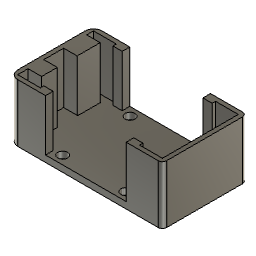
Machine2 (Autodesk Fusion 360 archive; units mm, degrees)
design "9VBatteryBox"
Autodesk Fusion 360 part; units mm, degrees
sketch "スケッチ1" plane through (0, 0, 0) normal (0, 0, 1) x (1, 0, 0)
  line L0 (144.9399, 9.1944) -> (279.0278, 9.1944)
  line L1 (203.6278, 43.1944) -> (203.6278, 34.9671)
  line L2 (159.4515, 43.1944) -> (104.8278, 43.1944)
  line L3 (104.8278, 39.3843) -> (144.9399, 39.3843)
  line L4 (287, 55) -> (292, 55)
  line L5 (159.4515, 43.1944) -> (287, 43.1944)
  line L6 (144.9399, 39.3843) -> (144.9399, 4.9444)
  line L7 (144.9399, 39.3843) -> (144.9399, 43.1944)
  line L8 (117.0478, 43.1944) -> (117.0478, 30.8655)
  line L9 (238.7084, 9.1944) -> (238.7084, 4.9444)
  line L10 (104.8278, 34.9671) -> (144.9399, 34.9671)
  line L11 (104.8278, 30.8655) -> (144.9399, 30.8655)
  line L12 (134.0867, 43.1944) -> (134.0867, 30.8655)
  line L13 (104.8278, 18.8579) -> (144.9399, 18.8579)
  line L14 (144.9399, 34.9671) -> (203.6278, 34.9671)
  line L15 (203.6278, 34.9671) -> (203.6278, 9.1944)
  line L16 (203.6278, 21.9444) -> (292, 21.9444)
  line L17 (188.3904, 43.1944) -> (188.3904, 34.9671)
  line L18 (257.9467, 4.9444) -> (257.9467, 9.1944)
  line L19 (104.8278, 43.1944) -> (104.8278, 7.374)
  line L20 (203.6278, 9.1944) -> (203.6278, 5)
  line L21 (292.0278, 13.4444) -> (279.0278, 13.4444)
  line L22 (292, 5) -> (292, 77.25)
  line L23 (279.0278, 21.9444) -> (279.0278, 4.9444)
  line L24 (98.5, 10) -> (104.8278, 10)
  line L25 (104.8278, 7.374) -> (104.8278, 5)
  line L26 (287, 200) -> (10, 200)
  line L27 (292, 205) -> (5, 205)
  line L28 (10, 200) -> (10, 10)
  line L29 (5, 205) -> (5, 5)
  line L30 (10, 55) -> (5, 55)
  line L31 (5, 105) -> (15, 105)
  line L32 (5, 5) -> (292, 5)
  line L33 (10, 10) -> (98.5, 10)
  line L34 (48.5, 5) -> (48.5, 10)
  line L35 (98.5, 10) -> (98.5, 5)
  line L36 (10, 155) -> (5, 155)
  line L37 (48.5, 200) -> (48.5, 205)
  line L38 (98.5, 205) -> (98.5, 200)
  line L39 (148.5, 205) -> (148.5, 195)
  line L40 (287, 43.1944) -> (287, 200)
  line L41 (292, 77.25) -> (292, 205)
  line L42 (292, 105) -> (282, 105)
  line L43 (198.5, 205) -> (198.5, 200)
  line L44 (248.5, 200) -> (248.5, 205)
  line L45 (287, 155) -> (292, 155)
  line L46 (106.6389, 30.0526) -> (114.8305, 30.0526)
  line L47 (115.4156, 29.4675) -> (115.4156, 23.0314)
  line L48 (115.4156, 23.0314) -> (114.6794, 23.0314)
  line L49 (112.2568, 23.0314) -> (109.2123, 23.0314)
  line L50 (106.7919, 23.0314) -> (106.0539, 23.0314)
  line L51 (106.0539, 23.0314) -> (106.0539, 29.4675)
  spline S0 degree 3 poles (114.8305, 30.0526) (115.1527, 30.0526) (115.4156, 29.7898) (115.4156, 29.4675) knots 0.055556 0.055556 0.055556 0.055556 0.111111 0.111111 0.111111 0.111111
  spline S1 degree 3 poles (114.6794, 23.0314) (114.6946, 23.0993) (114.7024, 23.1717) (114.7021, 23.2489) knots 0.222222 0.222222 0.222222 0.222222 0.277778 0.277778 0.277778 0.277778
  spline S2 degree 3 poles (114.7021, 23.2489) (114.7044, 23.8132) (114.2828, 24.1347) (113.5747, 24.1481) knots 0.277778 0.277778 0.277778 0.277778 0.333333 0.333333 0.333333 0.333333
  spline S3 degree 3 poles (113.5747, 24.1481) (112.9581, 24.1595) (112.3453, 23.8174) (112.1979, 23.7292) knots 0.333333 0.333333 0.333333 0.333333 0.388889 0.388889 0.388889 0.388889
  spline S4 degree 3 poles (112.1979, 23.7292) (112.2465, 23.5795) (112.273, 23.4198) (112.273, 23.2538) knots 0.388889 0.388889 0.388889 0.388889 0.444444 0.444444 0.444444 0.444444
  spline S5 degree 3 poles (112.273, 23.2538) (112.273, 23.1782) (112.2673, 23.104) (112.2568, 23.0314) knots 0.444444 0.444444 0.444444 0.444444 0.5 0.5 0.5 0.5
  spline S6 degree 3 poles (109.2123, 23.0314) (109.2017, 23.104) (109.1963, 23.1782) (109.1963, 23.2538) knots 0.555556 0.555556 0.555556 0.555556 0.611111 0.611111 0.611111 0.611111
  spline S7 degree 3 poles (109.1963, 23.2538) (109.1963, 23.4229) (109.2237, 23.5853) (109.2741, 23.7373) knots 0.611111 0.611111 0.611111 0.611111 0.666667 0.666667 0.666667 0.666667
  spline S8 degree 3 poles (109.2741, 23.7373) (109.1314, 23.823) (108.515, 24.1692) (107.8945, 24.1579) knots 0.666667 0.666667 0.666667 0.666667 0.722222 0.722222 0.722222 0.722222
  spline S9 degree 3 poles (107.8945, 24.1579) (107.1865, 24.1445) (106.7649, 23.823) (106.7672, 23.2587) knots 0.722222 0.722222 0.722222 0.722222 0.777778 0.777778 0.777778 0.777778
  spline S10 degree 3 poles (106.7672, 23.2587) (106.7669, 23.1778) (106.7752, 23.1021) (106.7919, 23.0314) knots 0.777778 0.777778 0.777778 0.777778 0.833333 0.833333 0.833333 0.833333
  spline S11 degree 3 poles (106.0539, 29.4675) (106.0539, 29.7898) (106.3167, 30.0526) (106.6389, 30.0526) knots 0.944444 0.944444 0.944444 0.944444 1 1 1 1
  spline S12 degree 3 poles (109.3634, 23.9517) (109.1948, 23.9942) (108.522, 24.1858) (108.0949, 24.6289) knots 0 0 0 0 0.2 0.2 0.2 0.2
  spline S13 degree 3 poles (108.0949, 24.6289) (107.6036, 25.139) (107.5329, 25.6644) (107.9335, 26.0619) knots 0.2 0.2 0.2 0.2 0.4 0.4 0.4 0.4
  spline S14 degree 3 poles (107.9335, 26.0619) (108.3311, 26.4624) (108.8564, 26.3917) (109.3665, 25.9005) knots 0.4 0.4 0.4 0.4 0.6 0.6 0.6 0.6
  spline S15 degree 3 poles (109.3665, 25.9005) (109.8123, 25.4709) (110.0034, 24.7921) (110.0444, 24.6287) knots 0.6 0.6 0.6 0.6 0.8 0.8 0.8 0.8
  spline S16 degree 3 poles (110.0444, 24.6287) (109.7516, 24.4814) (109.5122, 24.2435) (109.3634, 23.9517) knots 0.8 0.8 0.8 0.8 1 1 1 1
  spline S17 degree 3 poles (110.2591, 24.7171) (110.1709, 24.8646) (109.829, 25.4771) (109.8404, 26.094) knots 0 0 0 0 0.166667 0.166667 0.166667 0.166667
  spline S18 degree 3 poles (109.8404, 26.094) (109.8538, 26.8019) (110.1752, 27.2235) (110.7395, 27.2213) knots 0.166667 0.166667 0.166667 0.166667 0.333333 0.333333 0.333333 0.333333
  spline S19 degree 3 poles (110.7395, 27.2213) (111.3039, 27.2235) (111.6253, 26.8019) (111.6387, 26.094) knots 0.333333 0.333333 0.333333 0.333333 0.5 0.5 0.5 0.5
  spline S20 degree 3 poles (111.6387, 26.094) (111.65, 25.4734) (111.3039, 24.8569) (111.2184, 24.7144) knots 0.5 0.5 0.5 0.5 0.666667 0.666667 0.666667 0.666667
  spline S21 degree 3 poles (111.2184, 24.7144) (111.0662, 24.7647) (110.9035, 24.7921) (110.7347, 24.7921) knots 0.666667 0.666667 0.666667 0.666667 0.833333 0.833333 0.833333 0.833333
  spline S22 degree 3 poles (110.7347, 24.7921) (110.5688, 24.7921) (110.4089, 24.7658) (110.2591, 24.7171) knots 0.833333 0.833333 0.833333 0.833333 1 1 1 1
  spline S23 degree 3 poles (111.4325, 24.6249) (111.4749, 24.7933) (111.6665, 25.4664) (112.1097, 25.8936) knots 0 0 0 0 0.2 0.2 0.2 0.2
  spline S24 degree 3 poles (112.1097, 25.8936) (112.6197, 26.3848) (113.1452, 26.4555) (113.5426, 26.0549) knots 0.2 0.2 0.2 0.2 0.4 0.4 0.4 0.4
  spline S25 degree 3 poles (113.5426, 26.0549) (113.9432, 25.6574) (113.8724, 25.132) (113.3813, 24.6219) knots 0.4 0.4 0.4 0.4 0.6 0.6 0.6 0.6
  spline S26 degree 3 poles (113.3813, 24.6219) (112.9516, 24.1761) (112.2728, 23.9849) (112.1096, 23.9441) knots 0.6 0.6 0.6 0.6 0.8 0.8 0.8 0.8
  spline S27 degree 3 poles (112.1096, 23.9441) (111.9622, 24.2367) (111.7244, 24.476) (111.4325, 24.6249) knots 0.8 0.8 0.8 0.8 1 1 1 1
  line L52 (223.6183, 98.7307) -> (218.9513, 101.4249)
  line L53 (274.9744, 80.257) -> (274.9744, 93.3217)
  line L54 (178.3634, 124.8558) -> (173.6965, 127.5499)
  line L55 (159.2013, 133.9005) -> (159.2013, 100.259)
  spline S28 degree 3 poles (177.0807, 117.3528) (177.1468, 117.3877) (177.3767, 117.5094) (177.7645, 117.7871) (178.2366, 118.1785) (178.689, 118.628) (179.1161, 119.1237) (179.512, 119.6598) (179.8714, 120.2282) (180.1894, 120.8211) (180.4616, 121.4303) (180.684, 122.0475) (180.8534, 122.6643) (180.966, 123.2721) (181.0116, 123.7473) (181.0152, 124.0151) (181.0162, 124.0928) knots 0 0 0 0 0.031575 0.109833 0.188038 0.266123 0.344083 0.421947 0.499754 0.577553 0.655385 0.733293 0.811326 0.889534 0.967956 1 1 1 1
  spline S29 degree 3 poles (181.0162, 124.0928) (181.0145, 124.1922) (181.0095, 124.4798) (180.9541, 124.9309) (180.8293, 125.4266) (180.6418, 125.8715) (180.3971, 126.2601) (180.0948, 126.5734) (179.8692, 126.76) (179.7374, 126.82) (179.7335, 126.8218) knots 0 0 0 0 0.082093 0.237396 0.392753 0.547179 0.699572 0.849018 0.995492 1 1 1 1
  line L56 (179.739, 126.82) -> (172.9508, 130.7388)
  spline S30 degree 3 poles (177.0233, 125.6294) (177.0895, 125.672) (177.2938, 125.8032) (177.6296, 125.954) (178.0198, 126.082) (178.3856, 126.1403) (178.7205, 126.1324) (178.9934, 126.0774) (179.139, 125.999) (179.1983, 125.9671) knots 0 0 0 0 0.077027 0.237559 0.397851 0.558376 0.720409 0.8862 1 1 1 1
  line L57 (191.7004, 133.5787) -> (196.8468, 140.1409)
  line L58 (191.8248, 126.7682) -> (191.7058, 133.5856)
  line L59 (196.7999, 140.081) -> (201.8926, 139.7804)
  line L60 (191.1308, 126.0582) -> (196.9749, 125.7132)
  line L61 (202.7184, 132.9443) -> (202.5866, 140.4904)
  line L62 (197.0978, 125.7686) -> (202.7132, 132.9287)
  line L63 (174.9593, 93.4835) -> (174.9593, 123.3689)
  line L64 (174.9593, 93.4835) -> (215.5473, 70.0526)
  line L65 (215.5473, 99.9379) -> (215.5473, 70.0526)
  line L66 (215.5473, 99.9379) -> (231.5279, 90.7125)
  line L67 (231.5279, 70.1357) -> (231.5279, 90.7125)
  line L68 (231.6693, 70.0541) -> (231.5279, 70.1357)
  line L69 (231.6693, 56.9894) -> (231.6693, 70.0541)
  line L70 (160.9586, 97.8098) -> (231.6693, 56.9894)
  line L71 (160.9586, 131.4513) -> (160.9586, 97.8098)
  line L72 (160.9586, 131.4513) -> (174.9593, 123.3689)
  line L73 (233.6492, 71.3603) -> (231.5279, 70.1357)
  line L74 (233.6492, 91.9371) -> (231.5279, 90.7125)
  line L75 (233.6492, 71.3603) -> (233.6492, 91.9371)
  line L76 (222.3355, 98.4684) -> (233.6492, 91.9371)
  line L77 (215.5473, 99.9379) -> (217.9514, 101.3258)
  line L78 (222.6183, 98.6317) -> (217.9514, 101.3258)
  line L79 (222.3355, 98.4684) -> (222.6183, 98.6317)
  arc A0 (224.0325, 97.815) -> (222.6183, 98.6317) centre (223.1704, 97.9549) ccw
  line L80 (224.0325, 97.4887) -> (224.0325, 97.815)
  arc A1 (218.9513, 101.4249) -> (217.9514, 101.3258) centre (218.5373, 100.5081) ccw
  line L81 (235.9119, 70.0541) -> (235.9119, 56.9894)
  arc A2 (231.6693, 56.9894) -> (235.9119, 56.9894) centre (233.7906, 61.0611) ccw
  arc A3 (231.6693, 70.0541) -> (235.9119, 70.0541) centre (233.7906, 74.1257) ccw
  line L82 (273.9543, 94.6279) -> (271.833, 93.4033)
  line L83 (273.9543, 94.6279) -> (274.0957, 94.5463)
  arc A4 (274.0957, 92.0971) -> (274.0957, 94.5463) centre (273.6179, 93.3217) ccw
  line L84 (274.0957, 92.0971) -> (235.9119, 70.0541)
  line L85 (271.9744, 93.3217) -> (233.7906, 71.2787)
  line L86 (271.833, 93.4033) -> (271.9744, 93.3217)
  line L87 (233.7906, 71.2787) -> (233.6492, 71.3603)
  line L88 (235.9119, 56.9894) -> (274.0957, 79.0324)
  line L89 (274.0957, 79.0324) -> (274.0957, 92.0971)
  line L90 (199.1424, 126.0581) -> (177.0807, 113.3222)
  line L91 (215.2644, 116.7511) -> (199.1424, 126.0581)
  line L92 (215.2644, 116.7511) -> (217.3857, 117.9757)
  line L93 (255.8524, 95.7694) -> (217.3857, 117.9757)
  line L94 (263.9121, 88.6674) -> (255.8524, 93.3202)
  line L95 (174.9593, 93.4835) -> (177.0807, 94.7081)
  line L96 (181.5402, 91.7624) -> (182.0222, 91.5942)
  line L97 (180.1208, 93.1179) -> (180.2445, 92.8007)
  line L98 (180.7462, 92.2208) -> (181.1112, 91.9731)
  line L99 (186.5059, 92.2878) -> (186.7777, 92.5726)
  line L100 (186.1586, 92.0318) -> (186.5059, 92.2878)
  line L101 (182.1496, 95.2443) -> (181.6562, 95.0874)
  line L102 (184.355, 95.373) -> (183.7974, 95.4186)
  line L103 (186.252, 94.7109) -> (185.8537, 94.9409)
  line L104 (185.2746, 91.632) -> (185.7446, 91.8113)
  line L105 (182.6802, 95.3535) -> (182.1496, 95.2443)
  line L106 (183.2342, 95.4121) -> (182.6802, 95.3535)
  line L107 (187.0797, 93.5238) -> (187.0005, 93.8458)
  line L108 (185.7446, 91.8113) -> (186.1586, 92.0318)
  line L109 (184.8928, 95.2762) -> (184.355, 95.373)
  line L110 (183.7974, 95.4186) -> (183.2342, 95.4121)
  line L111 (182.5448, 91.4728) -> (183.0943, 91.4014)
  line L112 (187.0005, 93.8458) -> (186.8329, 94.1562)
  line L113 (180.5203, 94.3766) -> (180.2892, 94.0801)
  line L114 (186.5813, 94.4471) -> (186.252, 94.7109)
  line L115 (186.9668, 92.8789) -> (187.0683, 93.1987)
  line L116 (184.761, 91.4986) -> (185.2746, 91.632)
  line L117 (183.6565, 91.3817) -> (184.2169, 91.4144)
  line L118 (180.0867, 93.4425) -> (180.1208, 93.1179)
  line L119 (181.1112, 91.9731) -> (181.5402, 91.7624)
  line L120 (183.0943, 91.4014) -> (183.6565, 91.3817)
  line L121 (180.4548, 92.4991) -> (180.7462, 92.2208)
  line L122 (186.7777, 92.5726) -> (186.9668, 92.8789)
  line L123 (184.2169, 91.4144) -> (184.761, 91.4986)
  line L124 (181.6562, 95.0874) -> (181.2128, 94.8869)
  line L125 (180.1434, 93.766) -> (180.0867, 93.4425)
  line L126 (185.8537, 94.9409) -> (185.3967, 95.1309)
  line L127 (186.8329, 94.1562) -> (186.5813, 94.4471)
  line L128 (187.0683, 93.1987) -> (187.0797, 93.5238)
  line L129 (181.2128, 94.8869) -> (180.8309, 94.6479)
  line L130 (185.3967, 95.1309) -> (184.8928, 95.2762)
  line L131 (180.2892, 94.0801) -> (180.1434, 93.766)
  line L132 (180.8309, 94.6479) -> (180.5203, 94.3766)
  line L133 (180.2445, 92.8007) -> (180.4548, 92.4991)
  line L134 (182.0222, 91.5942) -> (182.5448, 91.4728)
  arc A5 (212.931, 73.6039) -> (215.5473, 73.0138) centre (215.3371, 78.1768) ccw
  line L135 (211.9066, 75.0733) -> (211.9406, 74.7488)
  line L136 (211.9406, 74.7488) -> (212.0643, 74.4315)
  line L137 (215.054, 77.0429) -> (214.5, 76.9843)
  line L138 (212.6507, 76.2787) -> (212.3401, 76.0075)
  line L139 (214.5, 76.9843) -> (213.9694, 76.8751)
  line L140 (215.5473, 77.0515) -> (215.054, 77.0429)
  line L141 (212.566, 73.8516) -> (212.931, 73.6039)
  line L142 (212.2746, 74.1299) -> (212.566, 73.8516)
  line L143 (212.0643, 74.4315) -> (212.2746, 74.1299)
  line L144 (212.109, 75.7109) -> (211.9632, 75.3968)
  line L145 (213.476, 76.7183) -> (213.0326, 76.5177)
  line L146 (212.3401, 76.0075) -> (212.109, 75.7109)
  line L147 (211.9632, 75.3968) -> (211.9066, 75.0733)
  line L148 (213.0326, 76.5177) -> (212.6507, 76.2787)
  line L149 (213.9694, 76.8751) -> (213.476, 76.7183)
  line L150 (251.5055, 93.0359) -> (251.9195, 93.2564)
  line L151 (252.8406, 94.7484) -> (252.7614, 95.0704)
  line L152 (252.7614, 95.0704) -> (252.5939, 95.3808)
  line L153 (252.5939, 95.3808) -> (252.3422, 95.6717)
  line L154 (245.9043, 94.9906) -> (245.8477, 94.6671)
  line L155 (247.4172, 96.3121) -> (246.9738, 96.1115)
  line L156 (248.8552, 92.626) -> (249.4174, 92.6063)
  line L157 (247.7832, 92.8188) -> (248.3057, 92.6974)
  line L158 (246.2813, 95.6012) -> (246.0501, 95.3047)
  line L159 (249.5583, 96.6433) -> (248.9951, 96.6367)
  line L160 (252.5386, 93.7972) -> (252.7277, 94.1035)
  line L161 (247.9105, 96.4689) -> (247.4172, 96.3121)
  line L162 (252.013, 95.9356) -> (251.6147, 96.1655)
  line L163 (252.7277, 94.1035) -> (252.8292, 94.4233)
  line L164 (251.0356, 92.8566) -> (251.5055, 93.0359)
  line L165 (250.5219, 92.7232) -> (251.0356, 92.8566)
  line L166 (247.3011, 92.987) -> (247.7832, 92.8188)
  line L167 (246.0501, 95.3047) -> (245.9043, 94.9906)
  line L168 (252.8292, 94.4233) -> (252.8406, 94.7484)
  line L169 (249.9779, 92.639) -> (250.5219, 92.7232)
  line L170 (245.8477, 94.6671) -> (245.8817, 94.3426)
  line L171 (246.5071, 93.4454) -> (246.8721, 93.1977)
  line L172 (251.9195, 93.2564) -> (252.2669, 93.5124)
  line L173 (249.4174, 92.6063) -> (249.9779, 92.639)
  line L174 (248.3057, 92.6974) -> (248.8552, 92.626)
  line L175 (246.9738, 96.1115) -> (246.5918, 95.8725)
  line L176 (248.9951, 96.6367) -> (248.4411, 96.5781)
  line L177 (252.2669, 93.5124) -> (252.5386, 93.7972)
  line L178 (246.2157, 93.7237) -> (246.5071, 93.4454)
  line L179 (246.8721, 93.1977) -> (247.3011, 92.987)
  line L180 (251.1577, 96.3555) -> (250.6537, 96.5008)
  line L181 (246.5918, 95.8725) -> (246.2813, 95.6012)
  line L182 (250.6537, 96.5008) -> (250.116, 96.5976)
  line L183 (250.116, 96.5976) -> (249.5583, 96.6433)
  line L184 (245.8817, 94.3426) -> (246.0054, 94.0253)
  line L185 (246.0054, 94.0253) -> (246.2157, 93.7237)
  line L186 (248.4411, 96.5781) -> (247.9105, 96.4689)
  line L187 (252.3422, 95.6717) -> (252.013, 95.9356)
  line L188 (251.6147, 96.1655) -> (251.1577, 96.3555)
  line L189 (214.0279, 113.0363) -> (214.0619, 112.7117)
  line L190 (214.772, 114.2417) -> (214.4615, 113.9704)
  line L191 (214.4615, 113.9704) -> (214.2303, 113.6739)
  line L192 (220.0997, 111.6256) -> (220.4471, 111.8816)
  line L193 (218.2962, 114.9668) -> (217.7385, 115.0124)
  line L194 (216.0907, 114.8381) -> (215.5973, 114.6812)
  line L195 (214.6873, 111.8146) -> (215.0523, 111.5669)
  line L196 (214.2303, 113.6739) -> (214.0845, 113.3598)
  line L197 (218.8339, 114.87) -> (218.2962, 114.9668)
  line L198 (216.6213, 114.9473) -> (216.0907, 114.8381)
  line L199 (214.3959, 112.0929) -> (214.6873, 111.8146)
  line L200 (220.7741, 113.75) -> (220.5224, 114.0409)
  line L201 (219.3378, 114.7247) -> (218.8339, 114.87)
  line L202 (215.154, 114.4807) -> (214.772, 114.2417)
  line L203 (214.0619, 112.7117) -> (214.1856, 112.3945)
  line L204 (219.7949, 114.5347) -> (219.3378, 114.7247)
  line L205 (220.9416, 113.4396) -> (220.7741, 113.75)
  line L206 (217.7385, 115.0124) -> (217.1753, 115.0059)
  line L207 (214.0845, 113.3598) -> (214.0279, 113.0363)
  line L208 (214.1856, 112.3945) -> (214.3959, 112.0929)
  line L209 (217.1753, 115.0059) -> (216.6213, 114.9473)
  line L210 (215.5973, 114.6812) -> (215.154, 114.4807)
  line L211 (220.1932, 114.3047) -> (219.7949, 114.5347)
  line L212 (220.5224, 114.0409) -> (220.1932, 114.3047)
  line L213 (219.6857, 111.4051) -> (220.0997, 111.6256)
  line L214 (217.0354, 110.9952) -> (217.5976, 110.9755)
  line L215 (218.7021, 111.0924) -> (219.2158, 111.2258)
  line L216 (215.0523, 111.5669) -> (215.4813, 111.3562)
  line L217 (217.5976, 110.9755) -> (218.1581, 111.0082)
  line L218 (219.2158, 111.2258) -> (219.6857, 111.4051)
  line L219 (218.1581, 111.0082) -> (218.7021, 111.0924)
  line L220 (220.9079, 112.4727) -> (221.0094, 112.7925)
  line L221 (220.4471, 111.8816) -> (220.7188, 112.1664)
  line L222 (215.4813, 111.3562) -> (215.9634, 111.188)
  line L223 (216.4859, 111.0666) -> (217.0354, 110.9952)
  line L224 (215.9634, 111.188) -> (216.4859, 111.0666)
  line L225 (220.7188, 112.1664) -> (220.9079, 112.4727)
  line L226 (221.0208, 113.1176) -> (220.9416, 113.4396)
  line L227 (221.0094, 112.7925) -> (221.0208, 113.1176)
  line L228 (273.9543, 115.2048) -> (257.9737, 124.4302)
  line L229 (273.9543, 115.2048) -> (271.833, 113.9802)
  line L230 (271.833, 113.9802) -> (260.5193, 120.5114)
  line L231 (260.2364, 120.3481) -> (260.5193, 120.5114)
  line L232 (255.5695, 123.0423) -> (260.2364, 120.3481)
  line L233 (255.5695, 123.0423) -> (257.9737, 124.4302)
  line L234 (271.833, 113.9802) -> (271.833, 93.4033)
  line L235 (255.8524, 93.3202) -> (255.8524, 115.8568)
  line L236 (260.5193, 113.4892) -> (260.5193, 120.5114)
  line L237 (273.9543, 115.2048) -> (273.9543, 94.6279)
  arc A6 (215.5473, 73.2954) -> (214.1149, 73.1546) centre (215.3976, 67.4618) ccw
  arc A7 (260.2364, 120.3481) -> (258.8222, 117.8987) centre (261.8926, 117.7589) ccw
  line L238 (258.8222, 117.8987) -> (254.1553, 120.5928)
  arc A8 (255.5695, 123.0423) -> (254.1553, 120.5928) centre (257.2257, 120.4531) ccw
  line L239 (260.2364, 113.3259) -> (260.5193, 113.4892)
  line L240 (258.8222, 117.4087) -> (260.2364, 113.3259)
  line L241 (258.8222, 117.4087) -> (258.8222, 117.8987)
  line L242 (254.1553, 120.1029) -> (258.8222, 117.4087)
  line L243 (254.1553, 120.1029) -> (254.1553, 120.5928)
  line L244 (260.2364, 113.3259) -> (255.5695, 116.02)
  line L245 (255.5695, 116.02) -> (254.1553, 120.1029)
  arc A9 (274.0957, 79.0324) -> (274.9744, 80.257) centre (273.4748, 80.4055) ccw
  line L246 (177.3635, 117.7345) -> (178.7777, 123.4502)
  line L247 (177.0807, 117.5712) -> (177.3635, 117.7345)
  line L248 (177.0807, 94.7081) -> (177.0807, 117.5712)
  line L249 (177.3635, 124.7568) -> (174.9593, 123.3689)
  arc A10 (178.7777, 123.9401) -> (177.3635, 124.7568) centre (177.9156, 124.0799) ccw
  line L250 (178.7777, 123.4502) -> (178.7777, 123.9401)
  arc A11 (160.9586, 136.3497) -> (160.9586, 131.4513) centre (161.8882, 133.9005) ccw
  line L251 (194.8997, 155.9435) -> (160.9586, 136.3497)
  arc A12 (203.385, 155.9435) -> (194.8997, 155.9435) centre (199.1424, 147.7553) ccw
  line L252 (217.3857, 147.8611) -> (214.9816, 146.4732)
  line L253 (210.3147, 149.1674) -> (214.9816, 146.4732)
  line L254 (210.5975, 149.3306) -> (210.3147, 149.1674)
  line L255 (210.5975, 149.3306) -> (199.1424, 155.9435)
  line L256 (199.1424, 155.9435) -> (160.9586, 133.9005)
  line L257 (160.9586, 133.9005) -> (172.4138, 127.2876)
  line L258 (172.6966, 127.4509) -> (172.4138, 127.2876)
  line L259 (177.3635, 124.7568) -> (172.6966, 127.4509)
  line L260 (217.3857, 147.8611) -> (203.385, 155.9435)
  arc A13 (173.6965, 127.5499) -> (172.6966, 127.4509) centre (173.2824, 126.6331) ccw
  arc A14 (159.2013, 100.259) -> (160.9586, 97.8098) centre (162.217, 100.5678) ccw
  line L261 (195.6803, 144.6252) -> (189.8164, 144.9714)
  line L262 (189.8164, 144.9714) -> (184.0861, 137.6647)
  line L263 (184.0861, 137.6647) -> (184.2197, 130.012)
  line L264 (199.1424, 155.9435) -> (199.1424, 142.6266)
  line L265 (199.1424, 128.3756) -> (199.1424, 126.0581)
  arc A15 (172.9508, 130.7388) -> (168.7788, 129.386) centre (171.8313, 127.0816) ccw
  arc A16 (184.877, 91.5238) -> (182.2951, 91.5238) centre (183.586, 85.8157) ccw
  arc A17 (250.6379, 92.7484) -> (248.056, 92.7484) centre (249.347, 87.0403) ccw
  line L266 (179.239, 125.954) -> (179.195, 125.9784)
  arc A18 (214.9816, 146.4732) -> (213.5674, 144.0237) centre (216.6378, 143.884) ccw
  line L267 (213.5674, 144.0237) -> (208.9005, 146.7179)
  arc A19 (210.3147, 149.1674) -> (208.9005, 146.7179) centre (211.9709, 146.5781) ccw
  line L268 (215.2644, 139.6142) -> (215.2644, 116.7511)
  line L269 (214.9816, 139.451) -> (215.2644, 139.6142)
  line L270 (213.5674, 143.5338) -> (214.9816, 139.451)
  line L271 (213.5674, 143.5338) -> (213.5674, 144.0237)
  line L272 (217.3857, 147.8611) -> (217.3857, 117.9757)
  line L273 (196.894, 140.516) -> (191.4432, 133.5658)
  ellipse E0 centre (191.1603, 133.7291) end of major axis (191.5614, 133.5945) minor radius 0.0991 (190.8743, 133.746) -> (191.4432, 133.5658) ccw
  line L274 (190.8743, 133.746) -> (196.6046, 141.0526)
  ellipse E1 centre (196.6111, 140.6793) end of major axis (196.433, 141.0745) minor radius 0.2411 (196.894, 140.516) -> (196.6046, 141.0526) ccw
  line L275 (196.6046, 141.0526) -> (189.8164, 144.9714)
  line L276 (190.8743, 133.746) -> (184.0861, 137.6647)
  line L277 (197.1449, 126.1438) -> (191.7101, 126.4646)
  line L278 (202.4559, 132.9158) -> (197.1449, 126.1438)
  line L279 (202.3321, 140.0086) -> (202.4559, 132.9158)
  line L280 (196.8972, 140.3294) -> (202.3321, 140.0086)
  line L281 (191.5862, 133.5574) -> (196.8972, 140.3294)
  line L282 (191.7101, 126.4646) -> (191.5862, 133.5574)
  line L283 (202.4718, 140.1868) -> (196.894, 140.516)
  line L284 (202.599, 132.9073) -> (202.4718, 140.1868)
  line L285 (197.1482, 125.9571) -> (202.599, 132.9073)
  line L286 (191.5703, 126.2864) -> (197.1482, 125.9571)
  line L287 (191.4432, 133.5658) -> (191.5703, 126.2864)
  line L288 (208.9005, 146.2279) -> (213.5674, 143.5338)
  line L289 (208.9005, 146.2279) -> (208.9005, 146.7179)
  ellipse E2 centre (191.3034, 133.7207) end of major axis (191.7044, 133.5861) minor radius 0.0991 (191.5862, 133.5574) -> (191.7004, 133.5787) ccw
  ellipse E3 centre (196.6144, 140.4927) end of major axis (196.4363, 140.8879) minor radius 0.2411 (196.8468, 140.1409) -> (196.8972, 140.3294) ccw
  line L290 (214.9816, 139.451) -> (210.3147, 142.1451)
  line L291 (210.3147, 142.1451) -> (208.9005, 146.2279)
  ellipse E4 centre (191.2874, 126.4496) end of major axis (191.6177, 126.7664) minor radius 0.32 (191.0079, 126.0932) -> (191.5703, 126.2864) ccw
  line L292 (191.0079, 126.0932) -> (190.8743, 133.746)
  line L293 (191.0079, 126.0932) -> (184.2197, 130.012)
  ellipse E5 centre (191.4272, 126.6279) end of major axis (191.7574, 126.9446) minor radius 0.32 (191.7101, 126.4646) -> (191.8248, 126.7682) ccw
  line L294 (196.6046, 141.0526) -> (202.4685, 140.7065)
  ellipse E6 centre (202.189, 140.3501) end of major axis (202.5192, 140.6669) minor radius 0.32 (202.4718, 140.1868) -> (202.4685, 140.7065) ccw
  line L295 (202.4685, 140.7065) -> (195.6803, 144.6252)
  ellipse E7 centre (202.0492, 140.1718) end of major axis (202.3795, 140.4886) minor radius 0.32 (201.8926, 139.7804) -> (202.3321, 140.0086) ccw
  ellipse E8 centre (196.8653, 126.1204) end of major axis (196.6872, 126.5156) minor radius 0.2411 (196.9749, 125.7132) -> (197.1482, 125.9571) ccw
  ellipse E9 centre (196.8621, 126.307) end of major axis (196.684, 126.7023) minor radius 0.2411 (197.1449, 126.1438) -> (196.8556, 126.6803) ccw
  line L296 (196.8556, 126.6803) -> (191.7751, 129.6132)
  ellipse E10 centre (202.1731, 133.079) end of major axis (202.5741, 132.9444) minor radius 0.0991 (201.887, 133.0959) -> (202.4559, 132.9158) ccw
  ellipse E11 centre (202.3161, 133.0706) end of major axis (202.7171, 132.936) minor radius 0.0991 (202.599, 132.9073) -> (202.7184, 132.9443) ccw
  line L297 (201.887, 133.0959) -> (194.6144, 137.2943)
  line L298 (196.8556, 126.6803) -> (201.887, 133.0959)
  arc A20 (218.8181, 111.1176) -> (216.2362, 111.1176) centre (217.5272, 105.3804) ccw
  line L299 (180.899, 123.9295) -> (180.8662, 124.4765)
  line L300 (178.9892, 126.5505) -> (178.5436, 126.5321)
  line L301 (178.5436, 126.5321) -> (178.0745, 126.4293)
  line L302 (177.0992, 125.9796) -> (176.7823, 125.7685)
  line L303 (179.4032, 126.4843) -> (178.9892, 126.5505)
  line L304 (179.7783, 126.3346) -> (179.4032, 126.4843)
  line L305 (178.0745, 126.4293) -> (177.5901, 126.244)
  line L306 (180.1078, 126.1042) -> (179.7783, 126.3346)
  line L307 (180.7684, 124.9759) -> (180.6073, 125.4187)
  line L308 (180.3857, 125.797) -> (180.1078, 126.1042)
  line L309 (180.6073, 125.4187) -> (180.3857, 125.797)
  line L310 (177.5901, 126.244) -> (177.0992, 125.9796)
  line L311 (180.8662, 124.4765) -> (180.7684, 124.9759)
  arc A21 (177.0807, 117.4823) -> (180.899, 123.9295) centre (173.0194, 124.242) ccw
  arc A22 (179.735, 126.8223) -> (176.2505, 126.0755) centre (178.5667, 123.7712) ccw
  arc A23 (177.3853, 117.8228) -> (180.7576, 123.8479) centre (173.0493, 124.2059) ccw
  line L312 (180.2429, 125.672) -> (180.4649, 125.3055)
  line L313 (180.4649, 125.3055) -> (180.6265, 124.8737)
  line L314 (176.9808, 125.7408) -> (177.4634, 126.0193)
  line L315 (176.9111, 125.6942) -> (176.9808, 125.7408)
  line L316 (180.7247, 124.3848) -> (180.7576, 123.8479)
  line L317 (179.9646, 125.9666) -> (180.2429, 125.672)
  line L318 (179.261, 126.3193) -> (179.6353, 126.1837)
  line L319 (179.6353, 126.1837) -> (179.9646, 125.9666)
  line L320 (178.4061, 126.3373) -> (178.8487, 126.3708)
  line L321 (178.8487, 126.3708) -> (179.261, 126.3193)
  line L322 (180.6265, 124.8737) -> (180.7247, 124.3848)
  line L323 (177.9414, 126.2194) -> (178.4061, 126.3373)
  line L324 (177.4634, 126.0193) -> (177.9414, 126.2194)
  arc A24 (180.1919, 123.8479) -> (179.239, 125.954) centre (177.9026, 124.0807) ccw
  arc A25 (177.5949, 118.6696) -> (180.1919, 123.8479) centre (173.0362, 124.1963) ccw
  line L325 (191.8212, 126.9775) -> (196.8556, 126.6803)
  line L326 (201.887, 133.0959) -> (201.7702, 139.7876)
  arc A26 (39.3574, 150.6424) -> (39.1574, 150.8424) centre (39.1574, 150.6424) ccw
  arc A27 (39.1574, 145.2424) -> (39.3574, 145.4424) centre (39.1574, 145.4424) ccw
  line L327 (34.3574, 145.2424) -> (39.1574, 145.2424)
  line L328 (39.1574, 150.8424) -> (34.3574, 150.8424)
  line L329 (85.7574, 170.0424) -> (74.4574, 170.0424)
  line L330 (85.7574, 170.0424) -> (85.7574, 168.5424)
  line L331 (85.7574, 168.5424) -> (77.7574, 168.5424)
  line L332 (77.7574, 168.3424) -> (77.7574, 168.5424)
  line L333 (74.4574, 168.3424) -> (77.7574, 168.3424)
  line L334 (74.4574, 168.3424) -> (74.4574, 170.0424)
  line L335 (77.7574, 141.5424) -> (85.7574, 141.5424)
  line L336 (85.7574, 141.5424) -> (85.7574, 140.0424)
  line L337 (74.4574, 140.0424) -> (85.7574, 140.0424)
  line L338 (74.4574, 140.0424) -> (74.4574, 141.7424)
  line L339 (77.7574, 141.7424) -> (74.4574, 141.7424)
  line L340 (77.7574, 141.5424) -> (77.7574, 141.7424)
  arc A28 (32.8574, 143.0424) -> (35.8574, 140.0424) centre (35.8574, 143.0424) ccw
  arc A29 (35.8574, 170.0424) -> (32.8574, 167.0424) centre (35.8574, 167.0424) ccw
  line L341 (45.7574, 170.0424) -> (45.7574, 168.3424)
  line L342 (42.4574, 168.3424) -> (45.7574, 168.3424)
  line L343 (42.4574, 168.5424) -> (42.4574, 168.3424)
  line L344 (42.4574, 168.5424) -> (34.3574, 168.5424)
  line L345 (34.3574, 141.5424) -> (42.4574, 141.5424)
  line L346 (45.7574, 141.7424) -> (42.4574, 141.7424)
  line L347 (45.7574, 141.7424) -> (45.7574, 140.0424)
  line L348 (35.8574, 140.0424) -> (45.7574, 140.0424)
  line L349 (32.8574, 167.0424) -> (32.8574, 143.0424)
  line L350 (45.7574, 170.0424) -> (35.8574, 170.0424)
  line L351 (42.4574, 141.7424) -> (42.4574, 141.5424)
  line L352 (34.3574, 168.5424) -> (34.3574, 141.5424)
  line L353 (45.7574, 168.3424) -> (45.7574, 167.3424)
  line L354 (45.7574, 167.3424) -> (42.4574, 167.3424)
  line L355 (42.4574, 167.3424) -> (42.4574, 168.3424)
  line L356 (42.4574, 142.7424) -> (45.7574, 142.7424)
  line L357 (45.7574, 142.7424) -> (45.7574, 141.7424)
  line L358 (42.4574, 141.7424) -> (42.4574, 142.7424)
  line L359 (77.7574, 168.3424) -> (77.7574, 167.3424)
  line L360 (77.7574, 167.3424) -> (74.4574, 167.3424)
  line L361 (74.4574, 167.3424) -> (74.4574, 168.3424)
  line L362 (74.4574, 142.7424) -> (77.7574, 142.7424)
  line L363 (77.7574, 142.7424) -> (77.7574, 141.7424)
  line L364 (74.4574, 141.7424) -> (74.4574, 142.7424)
  line L365 (39.1574, 161.9479) -> (34.3574, 161.9479)
  line L366 (39.1574, 157.8959) -> (39.1574, 161.9479)
  line L367 (39.1574, 157.8959) -> (34.3574, 157.8959)
  line L368 (39.3574, 165.8966) -> (39.3574, 161.9525)
  ellipse E12 centre (39.1574, 161.9525) end of major axis (39.3574, 161.9525) minor radius 0.0046 (39.1574, 161.9479) -> (39.3574, 161.9525) ccw
  line L369 (39.1574, 161.9479) -> (39.1574, 166.0943)
  ellipse E13 centre (39.1574, 165.8966) end of major axis (39.3574, 165.8966) minor radius 0.1977 (39.3574, 165.8966) -> (39.1574, 166.0943) ccw
  line L370 (39.1574, 166.0943) -> (34.3574, 166.0943)
  line L371 (39.3574, 161.9525) -> (39.3574, 158.0982)
  ellipse E14 centre (39.1574, 158.0982) end of major axis (39.1574, 158.3005) minor radius 0.2 (39.1574, 157.8959) -> (39.3574, 158.0982) ccw
  line L372 (39.3574, 150.6424) -> (39.3574, 145.4424)
  line L373 (39.1574, 166.0943) -> (39.1574, 166.1888)
  ellipse E15 centre (39.1574, 165.9865) end of major axis (39.1574, 166.1888) minor radius 0.2 (39.3574, 165.9865) -> (39.1574, 166.1888) ccw
  line L374 (39.3574, 165.9865) -> (39.3574, 165.8966)
  line L375 (39.1574, 166.1888) -> (34.3574, 166.1888)
  arc A30 (87.3574, 168.5424) -> (85.8574, 170.0424) centre (85.8574, 168.5424) ccw
  arc A31 (85.8574, 140.0424) -> (87.3574, 141.5424) centre (85.8574, 141.5424) ccw
  line L376 (87.3574, 168.5424) -> (87.3574, 141.5424)
  line L377 (85.8574, 168.5424) -> (85.8574, 141.5424)
  line L378 (85.8574, 140.0424) -> (85.7574, 140.0424)
  line L379 (85.7574, 170.0424) -> (85.8574, 170.0424)
  line L380 (85.8574, 141.5424) -> (85.7574, 141.5424)
  line L381 (85.7574, 168.5424) -> (85.8574, 168.5424)
  circle A32 centre (48.8574, 143.0424) radius 1.75
  circle A33 centre (71.3574, 143.0424) radius 1.75
  circle A34 centre (71.3574, 167.0424) radius 1.75
  circle A35 centre (48.8574, 167.0424) radius 1.75
  line L382 (45.7574, 140.0424) -> (74.4574, 140.0424)
  line L383 (74.4574, 170.0424) -> (45.7574, 170.0424)
  line L384 (39.1574, 145.2424) -> (39.1574, 150.8424)
  line L385 (48.8574, 143.0424) -> (48.8574, 145.5424)
  line L386 (48.8574, 143.0424) -> (46.3574, 143.0424)
  line L387 (48.8574, 143.0424) -> (48.8574, 140.5424)
  line L388 (48.8574, 143.0424) -> (51.3574, 143.0424)
  line L389 (48.8574, 145.5424) -> (48.8574, 147.2924)
  line L390 (46.3574, 143.0424) -> (44.6074, 143.0424)
  line L391 (48.8574, 140.5424) -> (48.8574, 138.7924)
  line L392 (51.3574, 143.0424) -> (53.1074, 143.0424)
  line L393 (71.3574, 143.0424) -> (71.3574, 145.5424)
  line L394 (71.3574, 143.0424) -> (68.8574, 143.0424)
  line L395 (71.3574, 143.0424) -> (71.3574, 140.5424)
  line L396 (71.3574, 143.0424) -> (73.8574, 143.0424)
  line L397 (71.3574, 145.5424) -> (71.3574, 147.2924)
  line L398 (68.8574, 143.0424) -> (67.1074, 143.0424)
  line L399 (71.3574, 140.5424) -> (71.3574, 138.7924)
  line L400 (73.8574, 143.0424) -> (75.6074, 143.0424)
  line L401 (71.3574, 167.0424) -> (71.3574, 169.5424)
  line L402 (71.3574, 167.0424) -> (68.8574, 167.0424)
  line L403 (71.3574, 167.0424) -> (71.3574, 164.5424)
  line L404 (71.3574, 167.0424) -> (73.8574, 167.0424)
  line L405 (71.3574, 169.5424) -> (71.3574, 171.2924)
  line L406 (68.8574, 167.0424) -> (67.1074, 167.0424)
  line L407 (71.3574, 164.5424) -> (71.3574, 162.7924)
  line L408 (73.8574, 167.0424) -> (75.6074, 167.0424)
  line L409 (48.8574, 167.0424) -> (48.8574, 169.5424)
  line L410 (48.8574, 167.0424) -> (46.3574, 167.0424)
  line L411 (48.8574, 167.0424) -> (48.8574, 164.5424)
  line L412 (48.8574, 167.0424) -> (51.3574, 167.0424)
  line L413 (48.8574, 169.5424) -> (48.8574, 171.2924)
  line L414 (46.3574, 167.0424) -> (44.6074, 167.0424)
  line L415 (48.8574, 164.5424) -> (48.8574, 162.7924)
  line L416 (51.3574, 167.0424) -> (53.1074, 167.0424)
  line L417 (45.7574, 72.9142) -> (45.7574, 91.2142)
  line L418 (45.7574, 72.9142) -> (74.4574, 72.9142)
  line L419 (74.4574, 91.2142) -> (74.4574, 72.9142)
  line L420 (74.4574, 91.2142) -> (85.7574, 91.2142)
  line L421 (85.7574, 78.6142) -> (85.7574, 91.2142)
  line L422 (85.8574, 78.6142) -> (85.7574, 78.6142)
  line L423 (85.8574, 70.6142) -> (85.8574, 78.6142)
  line L424 (35.8574, 70.6142) -> (85.8574, 70.6142)
  line L425 (35.8574, 91.2142) -> (35.8574, 70.6142)
  line L426 (35.8574, 91.2142) -> (45.7574, 91.2142)
  line L427 (32.8574, 70.6142) -> (32.8574, 91.2142)
  line L428 (32.8574, 91.2142) -> (35.8574, 91.2142)
  line L429 (35.8574, 70.6142) -> (32.8574, 70.6142)
  line L430 (87.3574, 78.6142) -> (87.3574, 70.6142)
  line L431 (87.3574, 70.6142) -> (85.8574, 70.6142)
  line L432 (85.8574, 78.6142) -> (87.3574, 78.6142)
  circle A36 centre (288.7099, 9.085) radius 1.12
  circle A37 centre (288.7099, 9.085) radius 2.72
  line L433 (279.2537, 9.1179) -> (291.9558, 9.1179)
  line L434 (284.6884, 11.7653) -> (284.6884, 6.3253)
  line L435 (280.0637, 10.1653) -> (280.0637, 7.9253)
  line L436 (280.0637, 7.9253) -> (284.6884, 6.3253)
  line L437 (284.6884, 11.7653) -> (280.0637, 10.1653)
  line L438 (288.7099, 12.4458) -> (288.7099, 5.8966)
  line L439 (139.033, 25.4909) -> (140.1747, 29.4147)
  line L440 (140.1747, 29.4147) -> (141.2298, 29.4147)
  line L441 (141.2298, 29.4147) -> (142.3708, 25.4909)
  line L442 (142.3708, 25.4909) -> (141.3374, 25.4909)
  line L443 (141.3374, 25.4909) -> (141.2164, 26.0102)
  line L444 (141.2164, 26.0102) -> (140.1828, 26.0102)
  line L445 (140.1828, 26.0102) -> (140.0572, 25.4909)
  line L446 (140.0572, 25.4909) -> (139.033, 25.4909)
  line L447 (140.3724, 26.8332) -> (141.0267, 26.8332)
  line L448 (141.0267, 26.8332) -> (140.7032, 28.1916)
  line L449 (140.7032, 28.1916) -> (140.3724, 26.8332)
  line L450 (137.472, 25.4909) -> (137.472, 26.943)
  line L451 (137.472, 26.943) -> (136.2777, 29.4147)
  line L452 (136.2777, 29.4147) -> (137.4322, 29.4147)
  line L453 (137.4322, 29.4147) -> (137.9926, 28.0771)
  line L454 (137.9926, 28.0771) -> (138.5567, 29.4147)
  line L455 (138.5567, 29.4147) -> (139.6803, 29.4147)
  line L456 (139.6803, 29.4147) -> (138.5144, 26.943)
  line L457 (138.5144, 26.943) -> (138.5144, 25.4909)
  line L458 (138.5144, 25.4909) -> (137.472, 25.4909)
  line L459 (133.5797, 25.4909) -> (134.7216, 29.4147)
  line L460 (134.7216, 29.4147) -> (135.7766, 29.4147)
  line L461 (135.7766, 29.4147) -> (136.9176, 25.4909)
  line L462 (136.9176, 25.4909) -> (135.8841, 25.4909)
  line L463 (135.8841, 25.4909) -> (135.7631, 26.0102)
  line L464 (135.7631, 26.0102) -> (134.7296, 26.0102)
  line L465 (134.7296, 26.0102) -> (134.6041, 25.4909)
  line L466 (134.6041, 25.4909) -> (133.5797, 25.4909)
  line L467 (134.9194, 26.8332) -> (135.5737, 26.8332)
  line L468 (135.5737, 26.8332) -> (135.2502, 28.1916)
  line L469 (135.2502, 28.1916) -> (134.9194, 26.8332)
  line L470 (130.4156, 25.4909) -> (130.4156, 29.4147)
  line L471 (130.4156, 29.4147) -> (131.4489, 29.4147)
  line L472 (131.4489, 29.4147) -> (131.4489, 28.1144)
  line L473 (131.4489, 28.1144) -> (132.3832, 29.4147)
  line L474 (132.3832, 29.4147) -> (133.5932, 29.4147)
  line L475 (133.5932, 29.4147) -> (132.4342, 27.9679)
  line L476 (132.4342, 27.9679) -> (133.7427, 25.4909)
  line L477 (133.7427, 25.4909) -> (132.5004, 25.4909)
  line L478 (132.5004, 25.4909) -> (131.7068, 27.0622)
  line L479 (131.7068, 27.0622) -> (131.4489, 26.7403)
  line L480 (131.4489, 26.7403) -> (131.4489, 25.4909)
  line L481 (131.4489, 25.4909) -> (130.4156, 25.4909)
  line L482 (126.9057, 25.4909) -> (126.9057, 29.4147)
  line L483 (126.9057, 29.4147) -> (127.8947, 29.4147)
  line L484 (127.8947, 29.4147) -> (128.805, 27.5895)
  line L485 (128.9681, 27.5634) -> (128.9681, 29.4147)
  line L486 (128.9681, 29.4147) -> (129.9617, 29.4147)
  line L487 (129.9617, 29.4147) -> (129.9617, 25.4909)
  line L488 (129.9617, 25.4909) -> (128.9681, 25.4909)
  line L489 (128.9681, 25.4909) -> (128.0579, 27.3024)
  line L490 (127.8947, 27.3286) -> (127.8947, 25.4909)
  line L491 (127.8947, 25.4909) -> (126.9057, 25.4909)
  line L492 (125.3735, 25.4909) -> (125.3735, 29.4147)
  line L493 (125.3735, 29.4147) -> (126.4353, 29.4147)
  line L494 (126.4353, 29.4147) -> (126.4353, 25.4909)
  line L495 (126.4353, 25.4909) -> (125.3735, 25.4909)
  line L496 (123.0416, 25.4909) -> (123.0416, 28.3808)
  line L497 (123.0416, 28.3808) -> (122.1075, 28.3808)
  line L498 (122.1075, 28.3808) -> (122.1075, 29.4147)
  line L499 (122.1075, 29.4147) -> (124.9986, 29.4147)
  line L500 (124.9986, 29.4147) -> (124.9986, 28.3808)
  line L501 (124.9986, 28.3808) -> (124.084, 28.3808)
  line L502 (124.084, 28.3808) -> (124.084, 25.4909)
  line L503 (124.084, 25.4909) -> (123.0416, 25.4909)
  line L504 (120.1691, 25.4909) -> (120.1691, 29.4147)
  line L505 (120.1691, 29.4147) -> (121.2115, 29.4147)
  line L506 (121.2115, 29.4147) -> (121.2115, 26.533)
  line L507 (121.2115, 26.533) -> (122.6284, 26.533)
  line L508 (122.6284, 26.533) -> (122.6284, 25.4909)
  line L509 (122.6284, 25.4909) -> (120.1691, 25.4909)
  line L510 (116.5334, 25.4909) -> (117.6751, 29.4147)
  line L511 (117.6751, 29.4147) -> (118.7304, 29.4147)
  line L512 (118.7304, 29.4147) -> (119.8713, 25.4909)
  line L513 (119.8713, 25.4909) -> (118.8378, 25.4909)
  line L514 (118.8378, 25.4909) -> (118.7168, 26.0102)
  line L515 (118.7168, 26.0102) -> (117.6834, 26.0102)
  line L516 (117.6834, 26.0102) -> (117.5579, 25.4909)
  line L517 (117.5579, 25.4909) -> (116.5334, 25.4909)
  line L518 (117.8728, 26.8332) -> (118.5272, 26.8332)
  line L519 (118.5272, 26.8332) -> (118.204, 28.1916)
  line L520 (118.204, 28.1916) -> (117.8728, 26.8332)
  spline S31 degree 3 poles (128.805, 27.5895) (128.8328, 27.5387) (128.8628, 27.4659) (128.8943, 27.3715) knots 0.166667 0.166667 0.166667 0.166667 0.222222 0.222222 0.222222 0.222222
  spline S32 degree 3 poles (128.8943, 27.3715) (128.9259, 27.2778) (128.9589, 27.164) (128.9945, 27.0305) knots 0.222222 0.222222 0.222222 0.222222 0.277778 0.277778 0.277778 0.277778
  spline S33 degree 3 poles (128.9945, 27.0305) (128.9854, 27.0997) (128.9793, 27.1758) (128.9748, 27.2595) knots 0.277778 0.277778 0.277778 0.277778 0.333333 0.333333 0.333333 0.333333
  spline S34 degree 3 poles (128.9748, 27.2595) (128.9704, 27.3433) (128.9681, 27.4441) (128.9681, 27.5634) knots 0.333333 0.333333 0.333333 0.333333 0.388889 0.388889 0.388889 0.388889
  spline S35 degree 3 poles (128.0579, 27.3024) (128.0301, 27.356) (127.9994, 27.4314) (127.9663, 27.5288) knots 0.666667 0.666667 0.666667 0.666667 0.722222 0.722222 0.722222 0.722222
  spline S36 degree 3 poles (127.9663, 27.5288) (127.933, 27.6262) (127.9, 27.7379) (127.8662, 27.8642) knots 0.722222 0.722222 0.722222 0.722222 0.777778 0.777778 0.777778 0.777778
  spline S37 degree 3 poles (127.8662, 27.8642) (127.8767, 27.7952) (127.8834, 27.7224) (127.8879, 27.6469) knots 0.777778 0.777778 0.777778 0.777778 0.833333 0.833333 0.833333 0.833333
  spline S38 degree 3 poles (127.8879, 27.6469) (127.8925, 27.5715) (127.8947, 27.4659) (127.8947, 27.3286) knots 0.833333 0.833333 0.833333 0.833333 0.888889 0.888889 0.888889 0.888889
extrude "押し出し1" add sketch "スケッチ1" along normal blind 2.3 contours A26 A27 L327 L328 L331 L332 L334 L335 L338 L340 L341 L343 L344 L345 L347 L351 L352 L353 L354 L355 L356 L357 L358 L359 L360 L361 L362 L363 L364 L367 L368 L371 E14 L372 E15 L374 L375 L377 L380 L381 L382 L383
extrude "押し出し2" add sketch "スケッチ1" along normal blind 20.6 contours L327 L328 L352 L384 | A28 A29 L341 L342 L343 L344 L345 L346 L347 L348 L349 L350 L351 L352 | L352 L365 L366 L367 | L352 L365 L369 L370 | L346 L356 L357 L358 | L342 L353 L354 L355 | L335 L336 L337 L338 L339 L340 | L330 L336 A30 A31 L376 L377 L378 L379 L380 L381 | L339 L362 L363 L364 | L329 L330 L331 L332 L333 L334 | L333 L359 L360 L361
